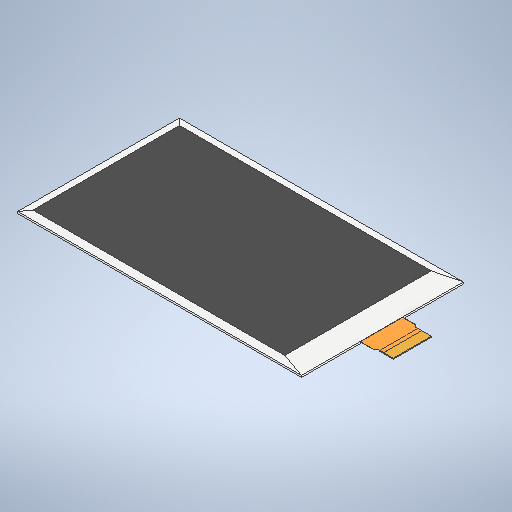
# Autodesk Inventor part: GDEY037T03
Saved by Autodesk Inventor 2025.2 (Build 292293000, 293)
## iProperties
Created: 2026-06-18
Part Number: GDEY037T03
Material: Generic
Document SubType Name: Modeling
Designer: Bruno
Density: 1 g/cm^3
Appearance: Default
Author: Bruno
Autodesk Inventor part; units mm, degrees
ref_plane "YZ Plane" through (0, 0, 0) normal (1, 0, 0) x (0, 1, 0)
ref_plane "XZ Plane" through (0, 0, 0) normal (0, 1, 0) x (-1, 0, 0)
ref_plane "XY Plane" through (0, 0, 0) normal (0, 0, 1) x (1, 0, 0)
sketch "Sketch1" plane through (0, 0, 0) normal (0, 1, 0) x (-1, 0, 0)
  line L0 (-46.5, 26.5) -> (46.5, 26.5)
  line L1 (46.5, 26.5) -> (46.5, -26.5)
  line L2 (46.5, -26.5) -> (-46.5, -26.5)
  line L3 (-46.5, -26.5) -> (-46.5, 26.5)
  line L4 (-46.5, 26.5) -> (46.5, -26.5) construction
  line L5 (46.5, 26.5) -> (-46.5, -26.5) construction
  point P0 (0, 0)
  dimension "d0" = 53
  dimension "d1" = 93
  constraints: 12 end point, 2 midpoint, 2 parallel, 1 horizontal, 1 perpendicular
  measures "d0" distance between parallel lines of L0 L2
  measures "d1" distance between parallel lines of L3 L1
extrude "Extrusion1" add sketch "Sketch1" along normal blind 1
sketch "Sketch2" plane through (0, 1, 0) normal (0, 1, 0) x (1, 0, 0)
  line L0 (46.5, -26.5) -> (46.5, 26.5) projected
  line L1 (46.5, -7.3) -> (50.85, -7.3)
  line L2 (50.85, -7.3) -> (51.55, -6.6)
  line L3 (51.55, -6.6) -> (56.65, -6.6)
  line L4 (56.65, -6.6) -> (56.65, 5.9)
  line L5 (56.65, 5.9) -> (51.55, 5.9)
  line L6 (51.55, 5.9) -> (50.85, 6.6)
  line L7 (50.85, 6.6) -> (46.5, 6.6)
  line L8 (53.5, -6.6) -> (53.5, 5.9) construction
  point P0 (0, 0)
  dimension "d4" = 12.5
  dimension "d7" = 19.9
  dimension "d8" = 10.15
  dimension "d9" = 3.15
  dimension "d10" = 0.7
  dimension "d11" = 0.7
  dimension "d12" = 5.1
  constraints: 16 end point, 5 perpendicular, 4 point on line, 2 vertical alignment, 1 horizontal, 1 parallel
  measures "d4" distance between parallel lines of L3 L5
  measures "d7" distance from line of L0.start L3
  measures "d8" distance between parallel lines of L0 L4
  measures "d9" distance between parallel lines of L4 L8
  measures "d10" distance between parallel lines of L7 L5
  measures "d11" distance between parallel lines of L1 L3
  measures "d12" distance of L5.end L4.end
extrude "Extrusion2" add sketch "Sketch2" against normal blind 0.7
sketch "Sketch3" plane through (0, 1, 0) normal (0, 1, 0) x (1, 0, 0)
  line L0 (46.5, 26.5) -> (-46.5, 26.5) projected
  line L1 (-46.5, 26.5) -> (-46.5, -26.5) projected
  line L2 (-46.5, -26.5) -> (46.5, -26.5) projected
  line L3 (46.5, -26.5) -> (46.5, -7.3) projected
  line L4 (46.5, -7.3) -> (50.85, -7.3) projected
  line L5 (50.85, -7.3) -> (51.55, -6.6) projected
  line L6 (51.55, -6.6) -> (56.65, -6.6) projected
  line L7 (56.65, -6.6) -> (56.65, 5.9) projected
  line L8 (56.65, 5.9) -> (51.55, 5.9) projected
  line L9 (51.55, 5.9) -> (50.85, 6.6) projected
  line L10 (50.85, 6.6) -> (46.5, 6.6) projected
  line L11 (46.5, 6.6) -> (46.5, 26.5) projected
  line L12 (46.5, 6.6) -> (46.5, 26.5) projected
  line L13 (46.5, -7.3) -> (46.5, 6.6)
  point P0 (0, 0)
  constraints: 2 end point, 1 vertical
extrude "Extrusion3" cut sketch "Sketch3" against normal blind 0.4 contours L10 L9 L8 L7 L6 L5 L4 L13
sketch "Sketch4" plane through (0, 0.3, 0) normal (0, -1, 0) x (1, 0, 0)
  line L0 (46.5, -6.6) -> (50.85, -6.6) projected
  line L1 (50.85, -6.6) -> (51.55, -5.9) projected
  line L2 (51.55, -5.9) -> (56.65, -5.9) projected
  line L3 (56.65, -5.9) -> (56.65, 6.6) projected
  line L4 (56.65, 6.6) -> (51.55, 6.6) projected
  line L5 (51.55, 6.6) -> (50.85, 7.3) projected
  line L6 (50.85, 7.3) -> (46.5, 7.3) projected
  line L7 (46.5, -6.6) -> (46.5, 7.3) projected
  line L8 (52.15, 6.6) -> (52.15, -5.9)
  point P0 (0, 0)
  dimension "d17" = 4.5
  constraints: 2 end point, 2 point on line, 1 perpendicular
  measures "d17" distance between parallel lines of L8 L3
extrude "Extrusion4" cut sketch "Sketch4" against normal blind 0.2 contours L7 L6 L5 L4 L8 L2 L1 L0
sketch "Sketch5" plane through (0, 0.6, 0) normal (0, 1, 0) x (1, 0, 0)
  line L0 (50.85, -7.3) -> (46.5, -7.3) projected
  line L1 (51.55, -6.6) -> (50.85, -7.3) projected
  line L2 (56.65, -6.6) -> (51.55, -6.6) projected
  line L3 (56.65, 5.9) -> (56.65, -6.6) projected
  line L4 (51.55, 5.9) -> (56.65, 5.9) projected
  line L5 (50.85, 6.6) -> (51.55, 5.9) projected
  line L6 (46.5, 6.6) -> (50.85, 6.6) projected
  line L7 (46.5, -7.3) -> (46.5, 6.6) projected
  line L8 (53.5, 5.9) -> (53.5, -6.6)
  point P0 (0, 0)
  dimension "d20" = 3.15
  constraints: 2 end point, 2 point on line, 1 perpendicular
  measures "d20" distance between parallel lines of L3 L8
extrude "Extrusion5" cut sketch "Sketch5" against normal blind 0.01 contours L8 L4 L3 L2
sketch "Sketch6" plane through (0, 1, 0) normal (0, 1, 0) x (1, 0, 0)
  line L0 (38.5, 24) -> (-44, 24)
  line L1 (-44, -24) -> (38.5, -24)
  line L2 (38.5, -24) -> (38.5, 24)
  line L3 (-36.8555, 0) -> (38.5, 0) construction
  line L4 (-44, -24) -> (-44, 24)
  line L5 (-46.5, 26.5) -> (-46.5, -26.5) construction
  point P0 (0, 0)
  dimension "d23" = 48
  dimension "d24" = 2.5
  dimension "d25" = 82.5
  constraints: 10 end point, 2 horizontal, 1 midpoint, 1 parallel, 1 point on line, 1 vertical
  measures "d23" distance between parallel lines of L0 L1
  measures "d24" distance between parallel lines of L5 L4
  measures "d25" distance between parallel lines of L4 L2
chamfer "Chamfer1" distance 2.5 distance2 0.4 3 edges at (0, 1, 26.5) (0, 1, -26.5) (-46.5, 1, 0) measured on face at (15.5, 1, -8.8333)
chamfer "Chamfer2" distance 8 distance2 0.4 1 edges at (46.5, 1, 0) measured on face at (16.3333, 1, -8)
body "Solid1"
